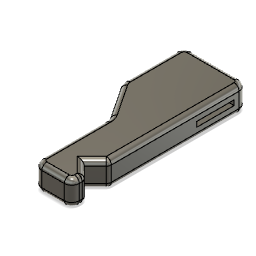
Winkelmesser_v1 (Autodesk Fusion 360 design; units mm, degrees)
Autodesk Fusion 360 part; units mm, degrees
sketch "Skizze1" plane through (0, 0, 0) normal (0, 1, 0) x (1, 0, 0)
  line L0 (0, 0) -> (25, 0)
  line L1 (25, 0) -> (25, -70)
  line L2 (25, -70) -> (0, -70)
  line L3 (0, -70) -> (0, 0)
  line L4 (25, -65) -> (20, -60)
  line L5 (20, -60) -> (25, -55)
  line L6 (10, -70) -> (10, -40)
  line L7 (10, -40) -> (0, -25)
  dimension "d1" = 70
  dimension "d2" = 25
  constraint horizontal L0
  constraint vertical L1
  constraint horizontal L2
  constraint vertical L3
  constraint coincident L0.start L3.end
  constraint coincident L1 L4.start
  constraint coincident L1 L5.end
  constraint perpendicular L4 L5
  constraint coincident L2 L6.start
  constraint perpendicular L2 L6
  constraint coincident L3 L7.end
  measures "d1" distance of L0.start L2.end
  measures "d2" distance of L0.start L0.end
extrude "Extrusion1" add sketch "Skizze1" along normal blind 10 contours L0 L1 L2 L3 L4 L5 L6 L7
sketch "Skizze2" plane through (25, 0, 0) normal (1, 0, 0) x (0, 0, -1)
  line L0 (-55, 0) -> (0, 0)
  line L1 (0, 0) -> (0, 10)
  line L2 (0, 10) -> (-55, 10)
  line L3 (-55, 10) -> (-55, 0)
  line L4 (-5, 6) -> (-20, 6)
  line L5 (-20, 6) -> (-20, 4)
  line L6 (-20, 4) -> (-5, 4)
  line L7 (-5, 4) -> (-5, 6)
  dimension "d5" = 5
  dimension "d6" = 4
  dimension "d7" = 2
  constraint horizontal L4
  constraint vertical L5
  constraint horizontal L6
  constraint vertical L7
  measures "d5" distance of L1 L7
  measures "d6" distance of L2 L4
  measures "d7" distance of L4.end L5.end
extrude "Extrusion2" cut sketch "Skizze2" against normal blind 30 contours L4 L5 L6 L7
fillet "Abrundung1" radius 5 2 edges at (0, 5, 25) (10, 5, 40)
fillet "Abrundung2" radius 3 2 edges at (10, 5, 70) (25, 5, 70)
fillet "Abrundung3" radius 2 2 edges at (25, 5, 55) (25, 5, 65)
fillet "Abrundung4" radius 3 2 edges at (0, 5, 0) (25, 5, 0)
fillet "Abrundung5" radius 2 1 faces at (19.8405, 10, 32.1837)
fillet "Abrundung6" radius 2 1 faces at (19.8405, 0, 32.1837)
